Autodesk Fusion 360 part; units mm, degrees
(part 2 of 2)
extrude "Cradle rear fixing (3)" cut sketch "Cradle rear fixing (2)" along normal blind 5 bodies 3 in component "03 Ivory rear cover"
ref_plane "WorkPlane11" through (0, 0, 88) normal (0, 0, 1) x (1, 0, 0) in component "08 Removable battery cradle"
sketch "Cradle M3 through hole (3)" plane through (0, 0, 88) normal (0, 0, 1) x (1, 0, 0) in component "08 Removable battery cradle"
  circle A0 centre (98, 139) radius 1.7
extrude "Cradle M3 through hole (4)" cut sketch "Cradle M3 through hole (3)" along normal blind 2 bodies 7 in component "08 Removable battery cradle"
ref_plane "WorkPlane24" through (0, 0, 90) normal (0, 0, 1) x (1, 0, 0) in component "03 Ivory rear cover"
sketch "Cradle spacer (3)" plane through (0, 0, 90) normal (0, 0, 1) x (1, 0, 0) in component "03 Ivory rear cover"
  circle A0 centre (98, 139) radius 3.5
extrude "Cradle spacer (4)" add sketch "Cradle spacer (3)" along normal blind 2 bodies 3 in component "03 Ivory rear cover"
ref_plane "WorkPlane25" through (0, 0, 90) normal (0, 0, 1) x (1, 0, 0) in component "03 Ivory rear cover"
sketch "Cradle rear fixing (3)" plane through (0, 0, 90) normal (0, 0, 1) x (1, 0, 0) in component "03 Ivory rear cover"
  circle A0 centre (98, 139) radius 1.7
extrude "Cradle rear fixing (4)" cut sketch "Cradle rear fixing (3)" along normal blind 5 bodies 3 in component "03 Ivory rear cover"
ref_plane "WorkPlane1" through (0, 0, 7.8) normal (0, 0, 1) x (1, 0, 0) in component "E01 Adafruit 2050 PCB - published tabs and holes"
sketch "PCB central outline - nominal thickness" plane through (0, 0, 7.8) normal (0, 0, 1) x (1, 0, 0) in component "E01 Adafruit 2050 PCB - published tabs and holes"
  line L0 (16.29, 93.06) -> (112.81, 93.06)
  line L1 (112.81, 93.06) -> (112.81, 148.94)
  line L2 (112.81, 148.94) -> (16.29, 148.94)
  line L3 (16.29, 148.94) -> (16.29, 93.06)
extrude "PCB central outline - nominal thickness (1)" add sketch "PCB central outline - nominal thickness" along normal blind 1.6 separate body makes body 8 in component "E01 Adafruit 2050 PCB - published tabs and holes"
ref_plane "WorkPlane2" through (0, 0, 7.8) normal (0, 0, 1) x (1, 0, 0) in component "E01 Adafruit 2050 PCB - published tabs and holes"
sketch "Mounting tabs bounding outline" plane through (0, 0, 7.8) normal (0, 0, 1) x (1, 0, 0) in component "E01 Adafruit 2050 PCB - published tabs and holes"
  line L0 (16.29, 87.98) -> (21.37, 87.98)
  line L1 (21.37, 87.98) -> (21.37, 154.02)
  line L2 (21.37, 154.02) -> (16.29, 154.02)
  line L3 (16.29, 154.02) -> (16.29, 87.98)
extrude "Mounting tabs bounding outline (1)" add sketch "Mounting tabs bounding outline" along normal blind 1.6 bodies 8 in component "E01 Adafruit 2050 PCB - published tabs and holes"
ref_plane "WorkPlane3" through (0, 0, 7.8) normal (0, 0, 1) x (1, 0, 0) in component "E01 Adafruit 2050 PCB - published tabs and holes"
sketch "Mounting tabs bounding outline (1)" plane through (0, 0, 7.8) normal (0, 0, 1) x (1, 0, 0) in component "E01 Adafruit 2050 PCB - published tabs and holes"
  line L0 (107.73, 87.98) -> (112.81, 87.98)
  line L1 (112.81, 87.98) -> (112.81, 154.02)
  line L2 (112.81, 154.02) -> (107.73, 154.02)
  line L3 (107.73, 154.02) -> (107.73, 87.98)
extrude "Mounting tabs bounding outline (2)" add sketch "Mounting tabs bounding outline (1)" along normal blind 1.6 bodies 8 in component "E01 Adafruit 2050 PCB - published tabs and holes"
ref_plane "WorkPlane4" through (0, 0, 7.8) normal (0, 0, 1) x (1, 0, 0) in component "E01 Adafruit 2050 PCB - published tabs and holes"
sketch "Published 3mm mounting hole" plane through (0, 0, 7.8) normal (0, 0, 1) x (1, 0, 0) in component "E01 Adafruit 2050 PCB - published tabs and holes"
  circle A0 centre (18.83, 90.52) radius 1.5
extrude "Published 3mm mounting hole (1)" cut sketch "Published 3mm mounting hole" along normal blind 1.6 bodies 8 in component "E01 Adafruit 2050 PCB - published tabs and holes"
ref_plane "WorkPlane5" through (0, 0, 7.8) normal (0, 0, 1) x (1, 0, 0) in component "E01 Adafruit 2050 PCB - published tabs and holes"
sketch "Published 3mm mounting hole (1)" plane through (0, 0, 7.8) normal (0, 0, 1) x (1, 0, 0) in component "E01 Adafruit 2050 PCB - published tabs and holes"
  circle A0 centre (18.83, 151.48) radius 1.5
extrude "Published 3mm mounting hole (2)" cut sketch "Published 3mm mounting hole (1)" along normal blind 1.6 bodies 8 in component "E01 Adafruit 2050 PCB - published tabs and holes"
ref_plane "WorkPlane6" through (0, 0, 7.8) normal (0, 0, 1) x (1, 0, 0) in component "E01 Adafruit 2050 PCB - published tabs and holes"
sketch "Published 3mm mounting hole (2)" plane through (0, 0, 7.8) normal (0, 0, 1) x (1, 0, 0) in component "E01 Adafruit 2050 PCB - published tabs and holes"
  circle A0 centre (110.27, 90.52) radius 1.5
extrude "Published 3mm mounting hole (3)" cut sketch "Published 3mm mounting hole (2)" along normal blind 1.6 bodies 8 in component "E01 Adafruit 2050 PCB - published tabs and holes"
ref_plane "WorkPlane7" through (0, 0, 7.8) normal (0, 0, 1) x (1, 0, 0) in component "E01 Adafruit 2050 PCB - published tabs and holes"
sketch "Published 3mm mounting hole (3)" plane through (0, 0, 7.8) normal (0, 0, 1) x (1, 0, 0) in component "E01 Adafruit 2050 PCB - published tabs and holes"
  circle A0 centre (110.27, 151.48) radius 1.5
extrude "Published 3mm mounting hole (4)" cut sketch "Published 3mm mounting hole (3)" along normal blind 1.6 bodies 8 in component "E01 Adafruit 2050 PCB - published tabs and holes"
ref_plane "WorkPlane1" through (0, 0, 3.8) normal (0, 0, 1) x (1, 0, 0) in component "E02 TFT glass and green active area"
sketch "Glass envelope - verify depth" plane through (0, 0, 3.8) normal (0, 0, 1) x (1, 0, 0) in component "E02 TFT glass and green active area"
  line L0 (22.17, 93.83) -> (106.87, 93.83)
  line L1 (106.87, 93.83) -> (106.87, 148.17)
  line L2 (106.87, 148.17) -> (22.17, 148.17)
  line L3 (22.17, 148.17) -> (22.17, 93.83)
extrude "Glass envelope - verify depth (1)" add sketch "Glass envelope - verify depth" along normal blind 4 separate body makes body 9 in component "E02 TFT glass and green active area"
ref_plane "WorkPlane1" through (0, 0, 3.7) normal (0, 0, 1) x (1, 0, 0) in component "REF Green TFT active area 480x320"
sketch "Published active area" plane through (0, 0, 3.7) normal (0, 0, 1) x (1, 0, 0) in component "REF Green TFT active area 480x320"
  line L0 (31.09, 96.52) -> (103.91, 96.52)
  line L1 (103.91, 96.52) -> (103.91, 145.48)
  line L2 (103.91, 145.48) -> (31.09, 145.48)
  line L3 (31.09, 145.48) -> (31.09, 96.52)
extrude "Published active area (1)" add sketch "Published active area" along normal blind 0.1 separate body makes body 10 in component "REF Green TFT active area 480x320"
ref_plane "WorkPlane1" through (0, 0, 9.4) normal (0, 0, 1) x (1, 0, 0) in component "E03 TFT rear headers and component keepout"
sketch "Header clearance" plane through (0, 0, 9.4) normal (0, 0, 1) x (1, 0, 0) in component "E03 TFT rear headers and component keepout"
  line L0 (17.58, 95.6) -> (20.08, 95.6)
  line L1 (20.08, 95.6) -> (20.08, 146.4)
  line L2 (20.08, 146.4) -> (17.58, 146.4)
  line L3 (17.58, 146.4) -> (17.58, 95.6)
extrude "Header clearance (1)" add sketch "Header clearance" along normal blind 8 separate body makes body 11 in component "E03 TFT rear headers and component keepout"
ref_plane "WorkPlane2" through (0, 0, 9.4) normal (0, 0, 1) x (1, 0, 0) in component "E03 TFT rear headers and component keepout"
sketch "Header clearance (1)" plane through (0, 0, 9.4) normal (0, 0, 1) x (1, 0, 0) in component "E03 TFT rear headers and component keepout"
  line L0 (108.512, 95.6) -> (111.012, 95.6)
  line L1 (111.012, 95.6) -> (111.012, 146.4)
  line L2 (111.012, 146.4) -> (108.512, 146.4)
  line L3 (108.512, 146.4) -> (108.512, 95.6)
extrude "Header clearance (2)" add sketch "Header clearance (1)" along normal blind 8 separate body makes body 12 in component "E03 TFT rear headers and component keepout"
ref_plane "WorkPlane3" through (0, 0, 9.4) normal (0, 0, 1) x (1, 0, 0) in component "E03 TFT rear headers and component keepout"
sketch "Display component envelope" plane through (0, 0, 9.4) normal (0, 0, 1) x (1, 0, 0) in component "E03 TFT rear headers and component keepout"
  line L0 (41, 103) -> (91, 103)
  line L1 (91, 103) -> (91, 136)
  line L2 (91, 136) -> (41, 136)
  line L3 (41, 136) -> (41, 103)
extrude "Display component envelope (1)" add sketch "Display component envelope" along normal blind 5 separate body makes body 13 in component "E03 TFT rear headers and component keepout"
ref_plane "WorkPlane1" through (0, 0, -16) normal (0, 0, 1) x (1, 0, 0) in component "REF Select knob"
sketch "Purchased knob" plane through (0, 0, -16) normal (0, 0, 1) x (1, 0, 0) in component "REF Select knob"
  circle A0 centre (36, 36) radius 11
extrude "Purchased knob (1)" add sketch "Purchased knob" along normal blind 13 separate body makes body 14 in component "REF Select knob"
ref_plane "WorkPlane1" through (0, 0, -16) normal (0, 0, 1) x (1, 0, 0) in component "REF Intensity knob"
sketch "Purchased knob (2)" plane through (0, 0, -16) normal (0, 0, 1) x (1, 0, 0) in component "REF Intensity knob"
  circle A0 centre (99, 36) radius 11
extrude "Purchased knob (1)'" add sketch "Purchased knob (2)" along normal blind 13 separate body makes body 15 in component "REF Intensity knob"
ref_plane "WorkPlane1" through (0, 0, -2) normal (0, 0, 1) x (1, 0, 0) in component "REF HOLD toggle"
sketch "Toggle washer" plane through (0, 0, -2) normal (0, 0, 1) x (1, 0, 0) in component "REF HOLD toggle"
  circle A0 centre (18, 70) radius 4
extrude "Toggle washer (1)" add sketch "Toggle washer" along normal blind 2 separate body makes body 16 in component "REF HOLD toggle"
ref_plane "WorkPlane2" through (0, 0, -15) normal (0, 0, 1) x (1, 0, 0) in component "REF HOLD toggle"
sketch "Toggle lever" plane through (0, 0, -15) normal (0, 0, 1) x (1, 0, 0) in component "REF HOLD toggle"
  circle A0 centre (18, 70) radius 1.5
extrude "Toggle lever (1)" add sketch "Toggle lever" along normal blind 13 separate body makes body 17 in component "REF HOLD toggle"
ref_plane "WorkPlane3" through (0, 0, 3) normal (0, 0, 1) x (1, 0, 0) in component "REF HOLD toggle"
sketch "Switch body" plane through (0, 0, 3) normal (0, 0, 1) x (1, 0, 0) in component "REF HOLD toggle"
  line L0 (13, 64) -> (23, 64)
  line L1 (23, 64) -> (23, 76)
  line L2 (23, 76) -> (13, 76)
  line L3 (13, 76) -> (13, 64)
extrude "Switch body (1)" add sketch "Switch body" along normal blind 17 separate body makes body 18 in component "REF HOLD toggle"
ref_plane "WorkPlane1" through (0, 0, -2) normal (0, 0, 1) x (1, 0, 0) in component "REF GRID toggle"
sketch "Toggle washer (2)" plane through (0, 0, -2) normal (0, 0, 1) x (1, 0, 0) in component "REF GRID toggle"
  circle A0 centre (117, 70) radius 4
extrude "Toggle washer (1)'" add sketch "Toggle washer (2)" along normal blind 2 separate body makes body 19 in component "REF GRID toggle"
ref_plane "WorkPlane2" through (0, 0, -15) normal (0, 0, 1) x (1, 0, 0) in component "REF GRID toggle"
sketch "Toggle lever (2)" plane through (0, 0, -15) normal (0, 0, 1) x (1, 0, 0) in component "REF GRID toggle"
  circle A0 centre (117, 70) radius 1.5
extrude "Toggle lever (1)'" add sketch "Toggle lever (2)" along normal blind 13 separate body makes body 20 in component "REF GRID toggle"
ref_plane "WorkPlane3" through (0, 0, 3) normal (0, 0, 1) x (1, 0, 0) in component "REF GRID toggle"
sketch "Switch body (2)" plane through (0, 0, 3) normal (0, 0, 1) x (1, 0, 0) in component "REF GRID toggle"
  line L0 (112, 64) -> (122, 64)
  line L1 (122, 64) -> (122, 76)
  line L2 (122, 76) -> (112, 76)
  line L3 (112, 76) -> (112, 64)
extrude "Switch body (1)'" add sketch "Switch body (2)" along normal blind 17 separate body makes body 21 in component "REF GRID toggle"
ref_plane "WorkPlane1" through (0, 0, 3) normal (0, 0, 1) x (1, 0, 0) in component "E04 Direct GPIO encoder body"
sketch "Encoder envelope" plane through (0, 0, 3) normal (0, 0, 1) x (1, 0, 0) in component "E04 Direct GPIO encoder body"
  line L0 (29.5, 29.5) -> (42.5, 29.5)
  line L1 (42.5, 29.5) -> (42.5, 42.5)
  line L2 (42.5, 42.5) -> (29.5, 42.5)
  line L3 (29.5, 42.5) -> (29.5, 29.5)
extrude "Encoder envelope (1)" add sketch "Encoder envelope" along normal blind 17 separate body makes body 22 in component "E04 Direct GPIO encoder body"
ref_plane "WorkPlane1" through (0, 0, 3) normal (0, 0, 1) x (1, 0, 0) in component "E05 B10K dial body"
sketch "Pot envelope" plane through (0, 0, 3) normal (0, 0, 1) x (1, 0, 0) in component "E05 B10K dial body"
  circle A0 centre (99, 36) radius 8.5
extrude "Pot envelope (1)" add sketch "Pot envelope" along normal blind 17 separate body makes body 23 in component "E05 B10K dial body"
ref_plane "WorkPlane1" through (0, 0, 64) normal (0, 0, 1) x (1, 0, 0) in component "E06 Drilled 33x61mm perfboard socket carrier"
sketch "Purchased perfboard trimmed below antenna" plane through (0, 0, 64) normal (0, 0, 1) x (1, 0, 0) in component "E06 Drilled 33x61mm perfboard socket carrier"
  line L0 (26, 12) -> (59, 12)
  line L1 (59, 12) -> (59, 61)
  line L2 (59, 61) -> (26, 61)
  line L3 (26, 61) -> (26, 12)
extrude "Purchased perfboard trimmed below antenna (1)" add sketch "Purchased perfboard trimmed below antenna" along normal blind 1.6 separate body makes body 24 in component "E06 Drilled 33x61mm perfboard socket carrier"
ref_plane "WorkPlane2" through (0, 0, 64) normal (0, 0, 1) x (1, 0, 0) in component "E06 Drilled 33x61mm perfboard socket carrier"
sketch "Drill carrier mount" plane through (0, 0, 64) normal (0, 0, 1) x (1, 0, 0) in component "E06 Drilled 33x61mm perfboard socket carrier"
  circle A0 centre (29, 16) radius 1.4
extrude "Drill carrier mount (1)" cut sketch "Drill carrier mount" along normal blind 1.6 bodies 24 in component "E06 Drilled 33x61mm perfboard socket carrier"
ref_plane "WorkPlane3" through (0, 0, 64) normal (0, 0, 1) x (1, 0, 0) in component "E06 Drilled 33x61mm perfboard socket carrier"
sketch "Drill carrier mount (1)" plane through (0, 0, 64) normal (0, 0, 1) x (1, 0, 0) in component "E06 Drilled 33x61mm perfboard socket carrier"
  circle A0 centre (29, 57) radius 1.4
extrude "Drill carrier mount (2)" cut sketch "Drill carrier mount (1)" along normal blind 1.6 bodies 24 in component "E06 Drilled 33x61mm perfboard socket carrier"
ref_plane "WorkPlane4" through (0, 0, 64) normal (0, 0, 1) x (1, 0, 0) in component "E06 Drilled 33x61mm perfboard socket carrier"
sketch "Drill carrier mount (2)" plane through (0, 0, 64) normal (0, 0, 1) x (1, 0, 0) in component "E06 Drilled 33x61mm perfboard socket carrier"
  circle A0 centre (56, 16) radius 1.4
extrude "Drill carrier mount (3)" cut sketch "Drill carrier mount (2)" along normal blind 1.6 bodies 24 in component "E06 Drilled 33x61mm perfboard socket carrier"
ref_plane "WorkPlane5" through (0, 0, 64) normal (0, 0, 1) x (1, 0, 0) in component "E06 Drilled 33x61mm perfboard socket carrier"
sketch "Drill carrier mount (3)" plane through (0, 0, 64) normal (0, 0, 1) x (1, 0, 0) in component "E06 Drilled 33x61mm perfboard socket carrier"
  circle A0 centre (56, 57) radius 1.4
extrude "Drill carrier mount (4)" cut sketch "Drill carrier mount (3)" along normal blind 1.6 bodies 24 in component "E06 Drilled 33x61mm perfboard socket carrier"
ref_plane "WorkPlane6" through (0, 0, 65.6) normal (0, 0, 1) x (1, 0, 0) in component "E06 Drilled 33x61mm perfboard socket carrier"
sketch "Female header socket envelope" plane through (0, 0, 65.6) normal (0, 0, 1) x (1, 0, 0) in component "E06 Drilled 33x61mm perfboard socket carrier"
  line L0 (30, 20) -> (32.5, 20)
  line L1 (32.5, 20) -> (32.5, 60.64)
  line L2 (32.5, 60.64) -> (30, 60.64)
  line L3 (30, 60.64) -> (30, 20)
extrude "Female header socket envelope (1)" add sketch "Female header socket envelope" along normal blind 7.4 separate body makes body 25 in component "E06 Drilled 33x61mm perfboard socket carrier"
ref_plane "WorkPlane7" through (0, 0, 65.6) normal (0, 0, 1) x (1, 0, 0) in component "E06 Drilled 33x61mm perfboard socket carrier"
sketch "Female header socket envelope (1)" plane through (0, 0, 65.6) normal (0, 0, 1) x (1, 0, 0) in component "E06 Drilled 33x61mm perfboard socket carrier"
  line L0 (52.86, 20) -> (55.36, 20)
  line L1 (55.36, 20) -> (55.36, 60.64)
  line L2 (55.36, 60.64) -> (52.86, 60.64)
  line L3 (52.86, 60.64) -> (52.86, 20)
extrude "Female header socket envelope (2)" add sketch "Female header socket envelope (1)" along normal blind 7.4 separate body makes body 26 in component "E06 Drilled 33x61mm perfboard socket carrier"
ref_plane "WorkPlane1" through (0, 0, 73) normal (0, 0, 1) x (1, 0, 0) in component "E07 ESP32-S3 DevKitC-1 N8R8 - fit envelope"
sketch "DevKitC nominal envelope - verify board" plane through (0, 0, 73) normal (0, 0, 1) x (1, 0, 0) in component "E07 ESP32-S3 DevKitC-1 N8R8 - fit envelope"
  line L0 (29.8, 13) -> (55.2, 13)
  line L1 (55.2, 13) -> (55.2, 75.5)
  line L2 (55.2, 75.5) -> (29.8, 75.5)
  line L3 (29.8, 75.5) -> (29.8, 13)
extrude "DevKitC nominal envelope - verify board (1)" add sketch "DevKitC nominal envelope - verify board" along normal blind 1.6 separate body makes body 27 in component "E07 ESP32-S3 DevKitC-1 N8R8 - fit envelope"
ref_plane "WorkPlane2" through (0, 0, 74.6) normal (0, 0, 1) x (1, 0, 0) in component "E07 ESP32-S3 DevKitC-1 N8R8 - fit envelope"
sketch "ESP module component envelope" plane through (0, 0, 74.6) normal (0, 0, 1) x (1, 0, 0) in component "E07 ESP32-S3 DevKitC-1 N8R8 - fit envelope"
  line L0 (33, 43) -> (51, 43)
  line L1 (51, 43) -> (51, 63)
  line L2 (51, 63) -> (33, 63)
  line L3 (33, 63) -> (33, 43)
extrude "ESP module component envelope (1)" add sketch "ESP module component envelope" along normal blind 3.4 separate body makes body 28 in component "E07 ESP32-S3 DevKitC-1 N8R8 - fit envelope"
ref_plane "WorkPlane3" through (0, 0, 74.6) normal (0, 0, 1) x (1, 0, 0) in component "E07 ESP32-S3 DevKitC-1 N8R8 - fit envelope"
sketch "USB sockets clearance" plane through (0, 0, 74.6) normal (0, 0, 1) x (1, 0, 0) in component "E07 ESP32-S3 DevKitC-1 N8R8 - fit envelope"
  line L0 (33, 13) -> (50, 13)
  line L1 (50, 13) -> (50, 20)
  line L2 (50, 20) -> (33, 20)
  line L3 (33, 20) -> (33, 13)
extrude "USB sockets clearance (1)" add sketch "USB sockets clearance" along normal blind 4 separate body makes body 29 in component "E07 ESP32-S3 DevKitC-1 N8R8 - fit envelope"
ref_plane "WorkPlane1" through (0, 0, 64) normal (0, 0, 1) x (1, 0, 0) in component "E08 PowerBoost 1000C - published PCB dimensions"
sketch "PowerBoost PCB without USB-A" plane through (0, 0, 64) normal (0, 0, 1) x (1, 0, 0) in component "E08 PowerBoost 1000C - published PCB dimensions"
  line L0 (70, 23) -> (106.068, 23)
  line L1 (106.068, 23) -> (106.068, 45.86)
  line L2 (106.068, 45.86) -> (70, 45.86)
  line L3 (70, 45.86) -> (70, 23)
extrude "PowerBoost PCB without USB-A (1)" add sketch "PowerBoost PCB without USB-A" along normal blind 1.6 separate body makes body 30 in component "E08 PowerBoost 1000C - published PCB dimensions"
ref_plane "WorkPlane2" through (0, 0, 64) normal (0, 0, 1) x (1, 0, 0) in component "E08 PowerBoost 1000C - published PCB dimensions"
sketch "Published charger fixing" plane through (0, 0, 64) normal (0, 0, 1) x (1, 0, 0) in component "E08 PowerBoost 1000C - published PCB dimensions"
  circle A0 centre (72.54, 25.54) radius 1.25
extrude "Published charger fixing (1)" cut sketch "Published charger fixing" along normal blind 1.6 bodies 30 in component "E08 PowerBoost 1000C - published PCB dimensions"
ref_plane "WorkPlane3" through (0, 0, 64) normal (0, 0, 1) x (1, 0, 0) in component "E08 PowerBoost 1000C - published PCB dimensions"
sketch "Published charger fixing (1)" plane through (0, 0, 64) normal (0, 0, 1) x (1, 0, 0) in component "E08 PowerBoost 1000C - published PCB dimensions"
  circle A0 centre (72.54, 43.32) radius 1.25
extrude "Published charger fixing (2)" cut sketch "Published charger fixing (1)" along normal blind 1.6 bodies 30 in component "E08 PowerBoost 1000C - published PCB dimensions"
ref_plane "WorkPlane4" through (0, 0, 65.6) normal (0, 0, 1) x (1, 0, 0) in component "E08 PowerBoost 1000C - published PCB dimensions"
sketch "JST battery socket envelope" plane through (0, 0, 65.6) normal (0, 0, 1) x (1, 0, 0) in component "E08 PowerBoost 1000C - published PCB dimensions"
  line L0 (76, 34) -> (87, 34)
  line L1 (87, 34) -> (87, 44)
  line L2 (87, 44) -> (76, 44)
  line L3 (76, 44) -> (76, 34)
extrude "JST battery socket envelope (1)" add sketch "JST battery socket envelope" along normal blind 7 separate body makes body 31 in component "E08 PowerBoost 1000C - published PCB dimensions"
ref_plane "WorkPlane5" through (0, 0, 65.6) normal (0, 0, 1) x (1, 0, 0) in component "E08 PowerBoost 1000C - published PCB dimensions"
sketch "Inductor and components envelope" plane through (0, 0, 65.6) normal (0, 0, 1) x (1, 0, 0) in component "E08 PowerBoost 1000C - published PCB dimensions"
  line L0 (84, 29) -> (102, 29)
  line L1 (102, 29) -> (102, 42)
  line L2 (102, 42) -> (84, 42)
  line L3 (84, 42) -> (84, 29)
extrude "Inductor and components envelope (1)" add sketch "Inductor and components envelope" along normal blind 5 separate body makes body 32 in component "E08 PowerBoost 1000C - published PCB dimensions"
ref_plane "WorkPlane6" through (0, 0, 65.6) normal (0, 0, 1) x (1, 0, 0) in component "E08 PowerBoost 1000C - published PCB dimensions"
sketch "Micro USB charging connector envelope" plane through (0, 0, 65.6) normal (0, 0, 1) x (1, 0, 0) in component "E08 PowerBoost 1000C - published PCB dimensions"
  line L0 (70, 30) -> (77, 30)
  line L1 (77, 30) -> (77, 38)
  line L2 (77, 38) -> (70, 38)
  line L3 (70, 38) -> (70, 30)
extrude "Micro USB charging connector envelope (1)" add sketch "Micro USB charging connector envelope" along normal blind 3 separate body makes body 33 in component "E08 PowerBoost 1000C - published PCB dimensions"
ref_plane "WorkPlane1" through (0, 0, 58) normal (0, 0, 1) x (1, 0, 0) in component "H01 Nylon 6mm board spacers"
sketch "M2.5 spacer" plane through (0, 0, 58) normal (0, 0, 1) x (1, 0, 0) in component "H01 Nylon 6mm board spacers"
  circle A0 centre (29, 16) radius 2.3
extrude "M2.5 spacer (1)" add sketch "M2.5 spacer" along normal blind 6 separate body makes body 34 in component "H01 Nylon 6mm board spacers"
ref_plane "WorkPlane2" through (0, 0, 58) normal (0, 0, 1) x (1, 0, 0) in component "H01 Nylon 6mm board spacers"
sketch "Spacer bore" plane through (0, 0, 58) normal (0, 0, 1) x (1, 0, 0) in component "H01 Nylon 6mm board spacers"
  circle A0 centre (29, 16) radius 1.4
extrude "Spacer bore (1)" cut sketch "Spacer bore" along normal blind 6 bodies 34 in component "H01 Nylon 6mm board spacers"
ref_plane "WorkPlane3" through (0, 0, 58) normal (0, 0, 1) x (1, 0, 0) in component "H01 Nylon 6mm board spacers"
sketch "M2.5 spacer (1)" plane through (0, 0, 58) normal (0, 0, 1) x (1, 0, 0) in component "H01 Nylon 6mm board spacers"
  circle A0 centre (29, 57) radius 2.3
extrude "M2.5 spacer (2)" add sketch "M2.5 spacer (1)" along normal blind 6 separate body makes body 35 in component "H01 Nylon 6mm board spacers"
ref_plane "WorkPlane4" through (0, 0, 58) normal (0, 0, 1) x (1, 0, 0) in component "H01 Nylon 6mm board spacers"
sketch "Spacer bore (1)" plane through (0, 0, 58) normal (0, 0, 1) x (1, 0, 0) in component "H01 Nylon 6mm board spacers"
  circle A0 centre (29, 57) radius 1.4
extrude "Spacer bore (2)" cut sketch "Spacer bore (1)" along normal blind 6 bodies 35 in component "H01 Nylon 6mm board spacers"
ref_plane "WorkPlane5" through (0, 0, 58) normal (0, 0, 1) x (1, 0, 0) in component "H01 Nylon 6mm board spacers"
sketch "M2.5 spacer (2)" plane through (0, 0, 58) normal (0, 0, 1) x (1, 0, 0) in component "H01 Nylon 6mm board spacers"
  circle A0 centre (56, 16) radius 2.3
extrude "M2.5 spacer (3)" add sketch "M2.5 spacer (2)" along normal blind 6 separate body makes body 36 in component "H01 Nylon 6mm board spacers"
ref_plane "WorkPlane6" through (0, 0, 58) normal (0, 0, 1) x (1, 0, 0) in component "H01 Nylon 6mm board spacers"
sketch "Spacer bore (2)" plane through (0, 0, 58) normal (0, 0, 1) x (1, 0, 0) in component "H01 Nylon 6mm board spacers"
  circle A0 centre (56, 16) radius 1.4
extrude "Spacer bore (3)" cut sketch "Spacer bore (2)" along normal blind 6 bodies 36 in component "H01 Nylon 6mm board spacers"
ref_plane "WorkPlane7" through (0, 0, 58) normal (0, 0, 1) x (1, 0, 0) in component "H01 Nylon 6mm board spacers"
sketch "M2.5 spacer (3)" plane through (0, 0, 58) normal (0, 0, 1) x (1, 0, 0) in component "H01 Nylon 6mm board spacers"
  circle A0 centre (56, 57) radius 2.3
extrude "M2.5 spacer (4)" add sketch "M2.5 spacer (3)" along normal blind 6 separate body makes body 37 in component "H01 Nylon 6mm board spacers"
ref_plane "WorkPlane8" through (0, 0, 58) normal (0, 0, 1) x (1, 0, 0) in component "H01 Nylon 6mm board spacers"
sketch "Spacer bore (3)" plane through (0, 0, 58) normal (0, 0, 1) x (1, 0, 0) in component "H01 Nylon 6mm board spacers"
  circle A0 centre (56, 57) radius 1.4
extrude "Spacer bore (4)" cut sketch "Spacer bore (3)" along normal blind 6 bodies 37 in component "H01 Nylon 6mm board spacers"
ref_plane "WorkPlane9" through (0, 0, 58) normal (0, 0, 1) x (1, 0, 0) in component "H01 Nylon 6mm board spacers"
sketch "M2.5 spacer (4)" plane through (0, 0, 58) normal (0, 0, 1) x (1, 0, 0) in component "H01 Nylon 6mm board spacers"
  circle A0 centre (72.54, 25.54) radius 2.3
extrude "M2.5 spacer (5)" add sketch "M2.5 spacer (4)" along normal blind 6 separate body makes body 38 in component "H01 Nylon 6mm board spacers"
ref_plane "WorkPlane10" through (0, 0, 58) normal (0, 0, 1) x (1, 0, 0) in component "H01 Nylon 6mm board spacers"
sketch "Spacer bore (4)" plane through (0, 0, 58) normal (0, 0, 1) x (1, 0, 0) in component "H01 Nylon 6mm board spacers"
  circle A0 centre (72.54, 25.54) radius 1.4
extrude "Spacer bore (5)" cut sketch "Spacer bore (4)" along normal blind 6 bodies 38 in component "H01 Nylon 6mm board spacers"
ref_plane "WorkPlane11" through (0, 0, 58) normal (0, 0, 1) x (1, 0, 0) in component "H01 Nylon 6mm board spacers"
sketch "M2.5 spacer (5)" plane through (0, 0, 58) normal (0, 0, 1) x (1, 0, 0) in component "H01 Nylon 6mm board spacers"
  circle A0 centre (72.54, 43.32) radius 2.3
extrude "M2.5 spacer (6)" add sketch "M2.5 spacer (5)" along normal blind 6 separate body makes body 39 in component "H01 Nylon 6mm board spacers"
ref_plane "WorkPlane12" through (0, 0, 58) normal (0, 0, 1) x (1, 0, 0) in component "H01 Nylon 6mm board spacers"
sketch "Spacer bore (5)" plane through (0, 0, 58) normal (0, 0, 1) x (1, 0, 0) in component "H01 Nylon 6mm board spacers"
  circle A0 centre (72.54, 43.32) radius 1.4
extrude "Spacer bore (6)" cut sketch "Spacer bore (5)" along normal blind 6 bodies 39 in component "H01 Nylon 6mm board spacers"
ref_plane "WorkPlane1" through (0, 0, 69) normal (0, 0, 1) x (1, 0, 0) in component "E10 Protected 1S 4400mAh battery - Adafruit 354 envelope"
sketch "Battery envelope" plane through (0, 0, 69) normal (0, 0, 1) x (1, 0, 0) in component "E10 Protected 1S 4400mAh battery - Adafruit 354 envelope"
  line L0 (24, 98.5) -> (93, 98.5)
  line L1 (93, 98.5) -> (93, 135.5)
  line L2 (93, 135.5) -> (24, 135.5)
  line L3 (24, 135.5) -> (24, 98.5)
extrude "Battery envelope (1)" add sketch "Battery envelope" along normal blind 18 separate body makes body 40 in component "E10 Protected 1S 4400mAh battery - Adafruit 354 envelope"
ref_plane "WorkPlane1" through (0, 0, 80) normal (0, 0, 1) x (1, 0, 0) in component "E11 Rear latching SPST power switch - 12mm"
sketch "Power switch body" plane through (0, 0, 80) normal (0, 0, 1) x (1, 0, 0) in component "E11 Rear latching SPST power switch - 12mm"
  circle A0 centre (117, 112) radius 7
extrude "Power switch body (1)" add sketch "Power switch body" along normal blind 12 separate body makes body 41 in component "E11 Rear latching SPST power switch - 12mm"
ref_plane "WorkPlane2" through (0, 0, 92) normal (0, 0, 1) x (1, 0, 0) in component "E11 Rear latching SPST power switch - 12mm"
sketch "Bushing" plane through (0, 0, 92) normal (0, 0, 1) x (1, 0, 0) in component "E11 Rear latching SPST power switch - 12mm"
  circle A0 centre (117, 112) radius 6
extrude "Bushing (1)" add sketch "Bushing" along normal blind 3 separate body makes body 42 in component "E11 Rear latching SPST power switch - 12mm"
ref_plane "WorkPlane3" through (0, 0, 95) normal (0, 0, 1) x (1, 0, 0) in component "E11 Rear latching SPST power switch - 12mm"
sketch "Switch cap" plane through (0, 0, 95) normal (0, 0, 1) x (1, 0, 0) in component "E11 Rear latching SPST power switch - 12mm"
  circle A0 centre (117, 112) radius 7
extrude "Switch cap (1)" add sketch "Switch cap" along normal blind 3 separate body makes body 43 in component "E11 Rear latching SPST power switch - 12mm"
ref_plane "WorkPlane1" through (0, 0, 83) normal (0, 0, 1) x (1, 0, 0) in component "E12 Panel charge USB extension - generic"
sketch "Panel extension" plane through (0, 0, 83) normal (0, 0, 1) x (1, 0, 0) in component "E12 Panel charge USB extension - generic"
  line L0 (52, 13.5) -> (83, 13.5)
  line L1 (83, 13.5) -> (83, 28.5)
  line L2 (83, 28.5) -> (52, 28.5)
  line L3 (52, 28.5) -> (52, 13.5)
extrude "Panel extension (1)" add sketch "Panel extension" along normal blind 9 separate body makes body 44 in component "E12 Panel charge USB extension - generic"
ref_plane "WorkPlane1" through (0, 0, 33) normal (0, 0, 1) x (1, 0, 0) in component "W01 SPI and direct control harness corridors"
sketch "Display SPI side corridor" plane through (0, 0, 33) normal (0, 0, 1) x (1, 0, 0) in component "W01 SPI and direct control harness corridors"
  line L0 (22, 40) -> (25, 40)
  line L1 (25, 40) -> (25, 125)
  line L2 (25, 125) -> (22, 125)
  line L3 (22, 125) -> (22, 40)
extrude "Display SPI side corridor (1)" add sketch "Display SPI side corridor" along normal blind 3 separate body makes body 45 in component "W01 SPI and direct control harness corridors"
ref_plane "WorkPlane2" through (0, 0, 17.4) normal (0, 0, 1) x (1, 0, 0) in component "W01 SPI and direct control harness corridors"
sketch "Display header service loop" plane through (0, 0, 17.4) normal (0, 0, 1) x (1, 0, 0) in component "W01 SPI and direct control harness corridors"
  line L0 (22, 121) -> (25, 121)
  line L1 (25, 121) -> (25, 124)
  line L2 (25, 124) -> (22, 124)
  line L3 (22, 124) -> (22, 121)
extrude "Display header service loop (1)" add sketch "Display header service loop" along normal blind 15.6 separate body makes body 46 in component "W01 SPI and direct control harness corridors"
ref_plane "WorkPlane3" through (0, 0, 33) normal (0, 0, 1) x (1, 0, 0) in component "W01 SPI and direct control harness corridors"
sketch "Controller harness corridor" plane through (0, 0, 33) normal (0, 0, 1) x (1, 0, 0) in component "W01 SPI and direct control harness corridors"
  line L0 (25, 40) -> (35, 40)
  line L1 (35, 40) -> (35, 43)
  line L2 (35, 43) -> (25, 43)
  line L3 (25, 43) -> (25, 40)
extrude "Controller harness corridor (1)" add sketch "Controller harness corridor" along normal blind 40 separate body makes body 47 in component "W01 SPI and direct control harness corridors"
ref_plane "WorkPlane1" through (0, 0, 74) normal (0, 0, 1) x (1, 0, 0) in component "W02 Charging USB cable corridor"
sketch "Rear charge USB service loop" plane through (0, 0, 74) normal (0, 0, 1) x (1, 0, 0) in component "W02 Charging USB cable corridor"
  line L0 (61, 21) -> (65, 21)
  line L1 (65, 21) -> (65, 34)
  line L2 (65, 34) -> (61, 34)
  line L3 (61, 34) -> (61, 21)
extrude "Rear charge USB service loop (1)" add sketch "Rear charge USB service loop" along normal blind 9 separate body makes body 48 in component "W02 Charging USB cable corridor"
ref_plane "WorkPlane2" through (0, 0, 68) normal (0, 0, 1) x (1, 0, 0) in component "W02 Charging USB cable corridor"
sketch "Charger USB approach" plane through (0, 0, 68) normal (0, 0, 1) x (1, 0, 0) in component "W02 Charging USB cable corridor"
  line L0 (61, 30) -> (70, 30)
  line L1 (70, 30) -> (70, 34)
  line L2 (70, 34) -> (61, 34)
  line L3 (61, 34) -> (61, 30)
extrude "Charger USB approach (1)" add sketch "Charger USB approach" along normal blind 6 separate body makes body 49 in component "W02 Charging USB cable corridor"
ref_plane "WorkPlane1" through (0, 0, 75) normal (0, 0, 1) x (1, 0, 0) in component "W03 Battery lead corridor - verify actual exit"
sketch "Battery lead to charger" plane through (0, 0, 75) normal (0, 0, 1) x (1, 0, 0) in component "W03 Battery lead corridor - verify actual exit"
  line L0 (88, 46) -> (91, 46)
  line L1 (91, 46) -> (91, 98.5)
  line L2 (91, 98.5) -> (88, 98.5)
  line L3 (88, 98.5) -> (88, 46)
extrude "Battery lead to charger (1)" add sketch "Battery lead to charger" along normal blind 3 separate body makes body 50 in component "W03 Battery lead corridor - verify actual exit"
ref_plane "WorkPlane1" through (0, 0, 87) normal (0, 0, 1) x (1, 0, 0) in component "H03 Soft battery pad and strap"
sketch "Insulating pad" plane through (0, 0, 87) normal (0, 0, 1) x (1, 0, 0) in component "H03 Soft battery pad and strap"
  line L0 (26, 100) -> (91, 100)
  line L1 (91, 100) -> (91, 134)
  line L2 (91, 134) -> (26, 134)
  line L3 (26, 134) -> (26, 100)
extrude "Insulating pad (1)" add sketch "Insulating pad" along normal blind 1 separate body makes body 51 in component "H03 Soft battery pad and strap"
ref_plane "WorkPlane2" through (0, 0, 67.5) normal (0, 0, 1) x (1, 0, 0) in component "H03 Soft battery pad and strap"
sketch "Strap front" plane through (0, 0, 67.5) normal (0, 0, 1) x (1, 0, 0) in component "H03 Soft battery pad and strap"
  line L0 (53, 98) -> (63, 98)
  line L1 (63, 98) -> (63, 136)
  line L2 (63, 136) -> (53, 136)
  line L3 (53, 136) -> (53, 98)
extrude "Strap front (1)" add sketch "Strap front" along normal blind 1 separate body makes body 52 in component "H03 Soft battery pad and strap"
ref_plane "WorkPlane3" through (0, 0, 68) normal (0, 0, 1) x (1, 0, 0) in component "H03 Soft battery pad and strap"
sketch "Strap wrap" plane through (0, 0, 68) normal (0, 0, 1) x (1, 0, 0) in component "H03 Soft battery pad and strap"
  line L0 (53, 97) -> (63, 97)
  line L1 (63, 97) -> (63, 98)
  line L2 (63, 98) -> (53, 98)
  line L3 (53, 98) -> (53, 97)
extrude "Strap wrap (1)" add sketch "Strap wrap" along normal blind 23 separate body makes body 53 in component "H03 Soft battery pad and strap"
ref_plane "WorkPlane4" through (0, 0, 68) normal (0, 0, 1) x (1, 0, 0) in component "H03 Soft battery pad and strap"
sketch "Strap wrap (1)" plane through (0, 0, 68) normal (0, 0, 1) x (1, 0, 0) in component "H03 Soft battery pad and strap"
  line L0 (53, 136) -> (63, 136)
  line L1 (63, 136) -> (63, 137)
  line L2 (63, 137) -> (53, 137)
  line L3 (53, 137) -> (53, 136)
extrude "Strap wrap (2)" add sketch "Strap wrap (1)" along normal blind 23 separate body makes body 54 in component "H03 Soft battery pad and strap"
ref_plane "WorkPlane5" through (0, 0, 90) normal (0, 0, 1) x (1, 0, 0) in component "H03 Soft battery pad and strap"
sketch "Strap rear" plane through (0, 0, 90) normal (0, 0, 1) x (1, 0, 0) in component "H03 Soft battery pad and strap"
  line L0 (53, 97) -> (63, 97)
  line L1 (63, 97) -> (63, 137)
  line L2 (63, 137) -> (53, 137)
  line L3 (53, 137) -> (53, 97)
extrude "Strap rear (1)" add sketch "Strap rear" along normal blind 1 separate body makes body 55 in component "H03 Soft battery pad and strap"
combine "Unify overlapping charger component keepouts" operation add target body 30 tool bodies 31 32 33 in component "E08 PowerBoost 1000C - published PCB dimensions"
ref_plane "WorkPlane8" through (0, 0, 64) normal (0, 0, 1) x (1, 0, 0) in component "E06 Drilled 33x61mm perfboard socket carrier"
sketch "Extend carrier for full 22-way sockets" plane through (0, 0, 64) normal (0, 0, 1) x (1, 0, 0) in component "E06 Drilled 33x61mm perfboard socket carrier"
  line L0 (26, 61) -> (59, 61)
  line L1 (59, 61) -> (59, 73)
  line L2 (59, 73) -> (26, 73)
  line L3 (26, 73) -> (26, 61)
extrude "Extend carrier for full 22-way sockets (1)" add sketch "Extend carrier for full 22-way sockets" along normal blind 1.6 bodies 24 in component "E06 Drilled 33x61mm perfboard socket carrier"
ref_plane "WorkPlane9" through (0, 0, 64) normal (0, 0, 1) x (1, 0, 0) in component "E06 Drilled 33x61mm perfboard socket carrier"
sketch "Carrier antenna clearance" plane through (0, 0, 64) normal (0, 0, 1) x (1, 0, 0) in component "E06 Drilled 33x61mm perfboard socket carrier"
  line L0 (33, 63) -> (52, 63)
  line L1 (52, 63) -> (52, 73)
  line L2 (52, 73) -> (33, 73)
  line L3 (33, 73) -> (33, 63)
extrude "Carrier antenna clearance (1)" cut sketch "Carrier antenna clearance" along normal blind 1.6 bodies 24 in component "E06 Drilled 33x61mm perfboard socket carrier"
ref_plane "WorkPlane10" through (0, 0, 65.6) normal (0, 0, 1) x (1, 0, 0) in component "E06 Drilled 33x61mm perfboard socket carrier"
sketch "Full 22-way socket envelope" plane through (0, 0, 65.6) normal (0, 0, 1) x (1, 0, 0) in component "E06 Drilled 33x61mm perfboard socket carrier"
  line L0 (30, 16) -> (32.5, 16)
  line L1 (32.5, 16) -> (32.5, 71.88)
  line L2 (32.5, 71.88) -> (30, 71.88)
  line L3 (30, 71.88) -> (30, 16)
extrude "Full 22-way socket envelope (1)" add sketch "Full 22-way socket envelope" along normal blind 7.4 bodies 24 25 in component "E06 Drilled 33x61mm perfboard socket carrier"
ref_plane "WorkPlane11" through (0, 0, 65.6) normal (0, 0, 1) x (1, 0, 0) in component "E06 Drilled 33x61mm perfboard socket carrier"
sketch "Full 22-way socket envelope (1)" plane through (0, 0, 65.6) normal (0, 0, 1) x (1, 0, 0) in component "E06 Drilled 33x61mm perfboard socket carrier"
  line L0 (52.86, 16) -> (55.36, 16)
  line L1 (55.36, 16) -> (55.36, 71.88)
  line L2 (55.36, 71.88) -> (52.86, 71.88)
  line L3 (52.86, 71.88) -> (52.86, 16)
extrude "Full 22-way socket envelope (2)" add sketch "Full 22-way socket envelope (1)" along normal blind 7.4 bodies 24 26 in component "E06 Drilled 33x61mm perfboard socket carrier"
ref_plane "WorkPlane5" through (0, 0, 0) normal (0, 0, 1) x (1, 0, 0) in component "04 Charcoal landscape bezel"
sketch "Restore bezel registration peg" plane through (0, 0, 0) normal (0, 0, 1) x (1, 0, 0) in component "04 Charcoal landscape bezel"
  circle A0 centre (28.7, 94.1) radius 0.9
extrude "Restore bezel registration peg (1)" add sketch "Restore bezel registration peg" along normal blind 2 bodies 4 in component "04 Charcoal landscape bezel"
ref_plane "WorkPlane6" through (0, 0, 0) normal (0, 0, 1) x (1, 0, 0) in component "04 Charcoal landscape bezel"
sketch "Restore bezel registration peg (1)" plane through (0, 0, 0) normal (0, 0, 1) x (1, 0, 0) in component "04 Charcoal landscape bezel"
  circle A0 centre (106.3, 147.9) radius 0.9
extrude "Restore bezel registration peg (2)" add sketch "Restore bezel registration peg (1)" along normal blind 2 bodies 4 in component "04 Charcoal landscape bezel"
component "01 Ivory front panel" placed x (1, 0, 0) y (0, 1, 0) z (0, 0, 1) at (0, 0, 0)
component "02 Ivory shell" placed x (1, 0, 0) y (0, 1, 0) z (0, 0, 1) at (0, 0, 0)
component "03 Ivory rear cover" placed x (1, 0, 0) y (0, 1, 0) z (0, 0, 1) at (0, 0, 0)
component "04 Charcoal landscape bezel" placed x (1, 0, 0) y (0, 1, 0) z (0, 0, 1) at (0, 0, 0)
component "05 Controller and charger tray" placed x (1, 0, 0) y (0, 1, 0) z (0, 0, 1) at (0, 0, 0)
component "07 Replaceable USB charge adapter - generic 24mm pitch" placed x (1, 0, 0) y (0, 1, 0) z (0, 0, 1) at (0, 0, 0)
component "08 Removable battery cradle" placed x (1, 0, 0) y (0, 1, 0) z (0, 0, 1) at (0, 0, 0)
component "E01 Adafruit 2050 PCB - published tabs and holes" placed x (1, 0, 0) y (0, 1, 0) z (0, 0, 1) at (0, 0, 0)
component "E02 TFT glass and green active area" placed x (1, 0, 0) y (0, 1, 0) z (0, 0, 1) at (0, 0, 0)
component "REF Green TFT active area 480x320" placed x (1, 0, 0) y (0, 1, 0) z (0, 0, 1) at (0, 0, 0)
component "E03 TFT rear headers and component keepout" placed x (1, 0, 0) y (0, 1, 0) z (0, 0, 1) at (0, 0, 0)
component "REF Select knob" placed x (1, 0, 0) y (0, 1, 0) z (0, 0, 1) at (0, 0, 0)
component "REF Intensity knob" placed x (1, 0, 0) y (0, 1, 0) z (0, 0, 1) at (0, 0, 0)
component "REF HOLD toggle" placed x (1, 0, 0) y (0, 1, 0) z (0, 0, 1) at (0, 0, 0)
component "REF GRID toggle" placed x (1, 0, 0) y (0, 1, 0) z (0, 0, 1) at (0, 0, 0)
component "E04 Direct GPIO encoder body" placed x (1, 0, 0) y (0, 1, 0) z (0, 0, 1) at (0, 0, 0)
component "E05 B10K dial body" placed x (1, 0, 0) y (0, 1, 0) z (0, 0, 1) at (0, 0, 0)
component "E06 Drilled 33x61mm perfboard socket carrier" placed x (1, 0, 0) y (0, 1, 0) z (0, 0, 1) at (0, 0, 0)
component "E07 ESP32-S3 DevKitC-1 N8R8 - fit envelope" placed x (1, 0, 0) y (0, 1, 0) z (0, 0, 1) at (0, 0, 0)
component "E08 PowerBoost 1000C - published PCB dimensions" placed x (1, 0, 0) y (0, 1, 0) z (0, 0, 1) at (0, 0, 0)
component "H01 Nylon 6mm board spacers" placed x (1, 0, 0) y (0, 1, 0) z (0, 0, 1) at (0, 0, 0)
component "E10 Protected 1S 4400mAh battery - Adafruit 354 envelope" placed x (1, 0, 0) y (0, 1, 0) z (0, 0, 1) at (0, 0, 0)
component "E11 Rear latching SPST power switch - 12mm" placed x (1, 0, 0) y (0, 1, 0) z (0, 0, 1) at (0, 0, 0)
component "E12 Panel charge USB extension - generic" placed x (1, 0, 0) y (0, 1, 0) z (0, 0, 1) at (0, 0, 0)
component "W01 SPI and direct control harness corridors" placed x (1, 0, 0) y (0, 1, 0) z (0, 0, 1) at (0, 0, 0)
component "W02 Charging USB cable corridor" placed x (1, 0, 0) y (0, 1, 0) z (0, 0, 1) at (0, 0, 0)
component "W03 Battery lead corridor - verify actual exit" placed x (1, 0, 0) y (0, 1, 0) z (0, 0, 1) at (0, 0, 0)
component "H03 Soft battery pad and strap" placed x (1, 0, 0) y (0, 1, 0) z (0, 0, 1) at (0, 0, 0)
